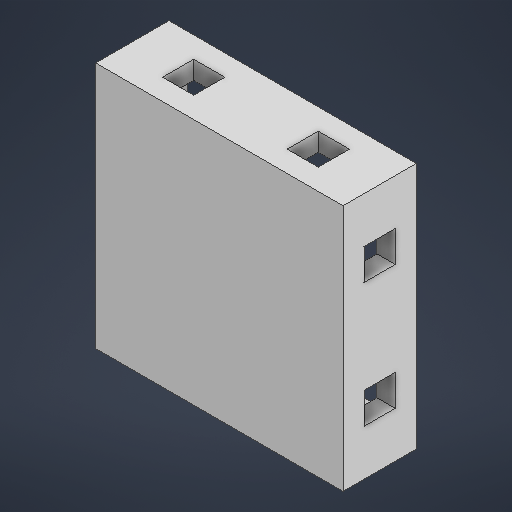
# Autodesk Inventor part: GORA
Saved by Autodesk Inventor 2026.1 (Build 301233020, 233B)
## iProperties
Created: 2026-09-26
Part Number: GORA
Material: Ogólny
Document SubType Name: Modeling
Designer: Bronh
Density: 1 g/cm^3
Appearance: Domyślna
Author: Bronh
Autodesk Inventor part; units mm, degrees
ref_plane "YZ Plane" through (0, 0, 0) normal (1, 0, 0) x (0, 1, 0)
ref_plane "XZ Plane" through (0, 0, 0) normal (0, 1, 0) x (-1, 0, 0)
ref_plane "XY Plane" through (0, 0, 0) normal (0, 0, 1) x (1, 0, 0)
sketch "Szkic1" plane through (0, 0, 0) normal (0, 0, 1) x (1, 0, 0)
  line L0 (0, 0) -> (135, 0)
  line L1 (135, 0) -> (135, 135)
  line L2 (135, 135) -> (0, 135)
  line L3 (0, 135) -> (0, 0)
  dimension "d0" = 135
  dimension "d1" = 135
  constraints: 8 end point, 2 parallel, 1 horizontal, 1 perpendicular
  measures "d0" distance of L2.end L1.end
  measures "d1" distance of L1.end L0.end
extrude "Wyciągnięcie proste1" add sketch "Szkic1" along normal blind 40
sketch "Szkic2" plane through (0, 135, 0) normal (0, 1, 0) x (1, 0, 0)
  line L0 (25, -11.5) -> (42, -11.5)
  line L1 (42, -11.5) -> (42, -28.5)
  line L2 (42, -28.5) -> (25, -28.5)
  line L3 (25, -28.5) -> (25, -11.5)
  line L4 (0, 0) -> (0, -40) projected
  line L5 (135, 0) -> (0, 0) projected
  point P0 (33.5, -11.5)
  dimension "d4" = 17
  dimension "d5" = 17
  dimension "d14" = 25
  dimension "d26" = 11.5
  constraints: 8 end point, 2 parallel, 1 horizontal, 1 midpoint, 1 perpendicular
  measures "d4" distance of L1.end L2.end
  measures "d5" distance of L0.end L1.end
  measures "d14" distance between parallel lines of L4 L3
  measures "d26" distance from line of point (33.5, -11.5) L5
extrude "Wyciągnięcie proste2" cut sketch "Szkic2" against normal blind 40
sketch "Szkic3" plane through (0, 0, 0) normal (0, 0, -1) x (-1, 0, 0)
  line L0 (-10, 10) -> (-125, 10)
  line L1 (-125, 10) -> (-125, 125)
  line L2 (-125, 125) -> (-10, 125)
  line L3 (-10, 125) -> (-10, 10)
  line L4 (-135, 0) -> (-135, 135) projected
  line L5 (0, 0) -> (-135, 0) projected
  dimension "d8" = 115
  dimension "d9" = 115
  dimension "d10" = 10
  dimension "d11" = 10
  constraints: 8 end point, 2 parallel, 1 horizontal, 1 perpendicular
  measures "d8" distance of L1.end L2.end
  measures "d9" distance of L0.end L1.end
  measures "d10" distance between parallel lines of L4 L1
  measures "d11" distance between parallel lines of L0 L5
extrude "Wyciągnięcie proste3" cut sketch "Szkic3" against normal blind 35
sketch "Szkic4" plane through (0, 135, 0) normal (0, 1, 0) x (1, 0, 0)
  line L0 (110, -28.5) -> (93, -28.5)
  line L1 (93, -28.5) -> (93, -11.5)
  line L2 (93, -11.5) -> (110, -11.5)
  line L3 (110, -11.5) -> (110, -28.5)
  line L4 (135, 0) -> (135, -40) projected
  line L5 (135, -40) -> (0, -40) projected
  point P0 (0, 0)
  dimension "d15" = 17
  dimension "d16" = 17
  dimension "d17" = 25
  dimension "d27" = 11.5
  constraints: 8 end point, 2 parallel, 1 horizontal, 1 perpendicular
  measures "d15" distance of L1.end L2.end
  measures "d16" distance of L0.end L1.end
  measures "d17" distance between parallel lines of L4 L3
  measures "d27" distance between parallel lines of L5 L0
extrude "Wyciągnięcie proste4" cut sketch "Szkic4" against normal blind 35
sketch "Szkic5" plane through (0, 0, 0) normal (-1, 0, 0) x (0, 0, 1)
  line L0 (11.5, 25) -> (28.5, 25)
  line L1 (28.5, 25) -> (28.5, 42)
  line L2 (28.5, 42) -> (11.5, 42)
  line L3 (11.5, 42) -> (11.5, 25)
  line L4 (11.5, 93) -> (28.5, 93)
  line L5 (28.5, 93) -> (28.5, 110)
  line L6 (28.5, 110) -> (11.5, 110)
  line L7 (11.5, 110) -> (11.5, 93)
  line L8 (0, 0) -> (40, 0) projected
  line L9 (0, 135) -> (40, 135) projected
  line L10 (0, 135) -> (0, 0) projected
  point P0 (20, 25)
  dimension "d20" = 17
  dimension "d21" = 17
  dimension "d22" = 17
  dimension "d23" = 17
  dimension "d24" = 25
  dimension "d25" = 25
  dimension "d28" = 11.5
  dimension "d29" = 11.5
  constraints: 16 end point, 4 parallel, 2 horizontal, 2 perpendicular, 1 midpoint
  measures "d20" distance of L2.end L1.end
  measures "d21" distance of L1.end L0.end
  measures "d22" distance of L6.end L5.end
  measures "d23" distance of L5.end L4.end
  measures "d24" distance from line of L8 point (20, 25)
  measures "d25" distance between parallel lines of L9 L6
  measures "d28" distance between parallel lines of L3 L10
  measures "d29" distance between parallel lines of L7 L10
extrude "Wyciągnięcie proste5" cut sketch "Szkic5" against normal blind 10
sketch "Szkic6" plane through (0, 0, 0) normal (0, -1, 0) x (1, 0, 0)
  line L0 (110, 28.5) -> (93, 28.5)
  line L1 (93, 28.5) -> (93, 11.5)
  line L2 (93, 11.5) -> (110, 11.5)
  line L3 (110, 11.5) -> (110, 28.5)
  line L4 (0, 40) -> (135, 40) projected
  line L5 (135, 0) -> (135, 40) projected
  line L6 (42, 11.5) -> (25, 11.5)
  line L7 (25, 11.5) -> (25, 28.5)
  line L8 (25, 28.5) -> (42, 28.5)
  line L9 (42, 28.5) -> (42, 11.5)
  line L10 (0, 0) -> (135, 0) projected
  line L11 (0, 0) -> (0, 40) projected
  dimension "d32" = 17
  dimension "d33" = 17
  dimension "d34" = 11.5
  dimension "d35" = 25
  dimension "d36" = 17
  dimension "d37" = 17
  dimension "d38" = 11.5
  dimension "d39" = 25
  constraints: 16 end point, 4 parallel, 2 horizontal, 2 perpendicular
  measures "d32" distance of L2.end L1.end
  measures "d33" distance of L1.end L0.end
  measures "d34" distance between parallel lines of L4 L0
  measures "d35" distance between parallel lines of L5 L3
  measures "d36" distance of L7.end L8.end
  measures "d37" distance of L6.end L7.end
  measures "d38" distance between parallel lines of L6 L10
  measures "d39" distance between parallel lines of L11 L7
extrude "Wyciągnięcie proste6" cut sketch "Szkic6" against normal blind 10 contours L3 L2 L1 L0 | L6 L7 L8 L9
sketch "Szkic7" plane through (135, 0, 0) normal (1, 0, 0) x (0, 0, -1)
  line L0 (-11.5, 110) -> (-28.5, 110)
  line L1 (-28.5, 110) -> (-28.5, 93)
  line L2 (-28.5, 93) -> (-11.5, 93)
  line L3 (-11.5, 93) -> (-11.5, 110)
  line L4 (-11.5, 42) -> (-28.5, 42)
  line L5 (-28.5, 42) -> (-28.5, 25)
  line L6 (-28.5, 25) -> (-11.5, 25)
  line L7 (-11.5, 25) -> (-11.5, 42)
  line L8 (0, 0) -> (0, 135) projected
  line L9 (0, 135) -> (-40, 135) projected
  line L10 (0, 0) -> (-40, 0) projected
  point P0 (-11.5, 101.5)
  point P1 (-20, 110)
  point P2 (-11.5, 33.5)
  dimension "d42" = 17
  dimension "d43" = 17
  dimension "d44" = 17
  dimension "d45" = 17
  dimension "d46" = 11.5
  dimension "d47" = 25
  dimension "d48" = 11.5
  dimension "d49" = 25
  constraints: 16 end point, 4 parallel, 3 midpoint, 2 horizontal, 2 perpendicular
  measures "d42" distance of L2.end L1.end
  measures "d43" distance of L1.end L0.end
  measures "d44" distance of L6.end L5.end
  measures "d45" distance of L5.end L4.end
  measures "d46" distance from line of L8 point (-11.5, 101.5)
  measures "d47" distance from line of L9 point (-20, 110)
  measures "d48" distance from line of L8 point (-11.5, 33.5)
  measures "d49" distance between parallel lines of L10 L6
extrude "Wyciągnięcie proste7" cut sketch "Szkic7" against normal blind 10
